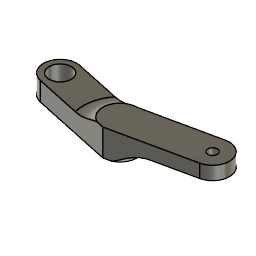
Left Control Arm (Autodesk Fusion 360 design; units mm, degrees)
Autodesk Fusion 360 part; units mm, degrees
sketch "Sketch1" plane through (0, 0, 0) normal (0, 0, 1) x (1, 0, 0)
  circle A0 centre (0, 0) radius 2.2
  circle A1 centre (28.829, 0) radius 0.9
  circle A2 centre (0, 0) radius 3.175
  circle A3 centre (28.829, 0) radius 3.175
  line L0 (28.161, 3.1039) -> (14.4145, 0.1454)
  line L1 (14.4145, 0.1454) -> (0.668, 3.1039)
  line L2 (29.497, -3.1039) -> (14.4145, -6.35)
  line L3 (14.4145, -6.35) -> (-0.668, -3.1039)
  dimension "d1" = 1.8
  dimension "d2" = 4.4
  dimension "d3" = 28.829
  dimension "d4" = 6.35
  dimension "d5" = 6.35
  dimension "d14" = 6.35
  constraint coincident A0.centre A2.centre
  constraint concentric A1 A3
  constraint horizontal A0.centre A1.centre
  constraint coincident A3 L0.start
  constraint coincident A2 L1.end
  constraint coincident A3 L2.start
  constraint parallel L0 L2
  constraint coincident A2 L3.end
  constraint tangent A2 L3
  constraint tangent A2 L1
  constraint tangent A3 L0
  constraint tangent A3 L2
  constraint parallel L1 L3
  constraint vertical L0.end L2.end
  measures "d1" diameter of A1
  measures "d2" diameter of A0
  measures "d3" distance of A0.centre A1.centre
  measures "d4" diameter of A3
  measures "d5" diameter of A2
  measures "d14" vertical distance of A1.centre L2.end
extrude "Extrude1" add sketch "Sketch1" along normal blind 2.54
sketch "Sketch3" plane through (0, 0, 0) normal (0, 0, -1) x (1, 0, 0)
  circle A0 centre (0, 0) radius 2.2
  circle A1 centre (28.829, 0) radius 0.9
  line L0 (0.668, -3.1039) -> (14.4145, -0.1454)
  line L1 (14.4145, -0.1454) -> (28.161, -3.1039)
  arc A2 (28.161, -3.1039) -> (29.497, 3.1039) centre (28.829, 0) ccw
  line L2 (29.497, 3.1039) -> (14.4145, 6.35)
  line L3 (14.4145, 6.35) -> (-0.668, 3.1039)
  arc A3 (-0.668, 3.1039) -> (0.668, -3.1039) centre (0, 0) ccw
  line L4 (14.4145, 6.35) -> (14.4145, -0.1454)
  circle A4 centre (0, 0) radius 3.175
  line L5 (14.4145, 6.35) -> (-0.668, 3.1039)
  line L6 (14.4145, -0.1454) -> (0.668, -3.1039)
  circle A5 centre (14.4145, 3.1023) radius 3.2477
  constraint coincident L2.end L3.start
  constraint coincident L0.end L1.start
  constraint coincident A0.centre A3.centre
  constraint coincident L3.end A3.start
  constraint tangent A4 L5
  constraint coincident L0.start A3.end
  constraint midpoint L4 A5.centre
  constraint coincident L2.end A5
extrude "Extrude3" add sketch "Sketch3" along normal blind 1.27 and the other way blind 1.905 contours L3 L4 L5 A5 | L2 L4 A5
sketch "Sketch2" plane through (0, 0, 0) normal (0, 0, -1) x (1, 0, 0)
  circle A0 centre (28.829, 0) radius 0.9
  arc A1 (28.161, -3.1039) -> (29.497, 3.1039) centre (28.829, 0) ccw
  circle A2 centre (0, 0) radius 2.0955
  circle A3 centre (0, 0) radius 3.175
  line L0 (14.4145, -0.1454) -> (28.161, -3.1039)
  line L1 (29.497, 3.1039) -> (15.7506, 6.0625)
  circle A4 centre (0, 0) radius 2.2
  line L2 (0.668, -3.1039) -> (14.4145, -0.1454)
  line L3 (13.0784, 6.0625) -> (-0.668, 3.1039)
  arc A5 (-0.668, 3.1039) -> (0.668, -3.1039) centre (0, 0) ccw
  arc A6 (14.4145, -0.1454) -> (15.7506, 6.0625) centre (14.4145, 3.1023) ccw
  arc A7 (13.0784, 6.0625) -> (14.4145, -0.1454) centre (14.4145, 3.1023) ccw
  dimension "d8" = 4.191
  dimension "d9" = 6.35
  measures "d8" diameter of A2
  measures "d9" diameter of A3
extrude "Extrude2" cut sketch "Sketch2" against normal blind 5.588 contours A3 L2 L3 A7 | A3 A5
sketch "Sketch4" plane through (0, 0, -1.27) normal (0, 0, -1) x (1, 0, 0)
  arc A0 (13.0784, 6.0625) -> (15.7506, 6.0625) centre (14.4145, 3.1023) ccw
  line L0 (15.7506, 6.0625) -> (14.4145, 6.35)
  line L1 (14.4145, 6.35) -> (13.0784, 6.0625)
  circle A1 centre (0, 0) radius 2.0955
  circle A2 centre (0, 0) radius 3.175
  line L2 (13.7465, 6.2062) -> (-0.668, 3.1039)
  line L3 (0.9727, -3.0223) -> (14.4145, -0.1454)
  dimension "d19" = 4.191
  dimension "d20" = 6.35
  dimension "d21" = 13.4418
  constraint coincident A1.centre A2.centre
  constraint concentric A1 A2
  constraint midpoint L1 L2.start
  constraint coincident A2 L2.end
  constraint tangent A2 L2
  constraint coincident A2 L3.start
  constraint midpoint A0 L3.end
  measures "d19" diameter of A1
  measures "d20" diameter of A2
  measures "d21" horizontal distance of L3.start L3.end
extrude "Extrude4" add sketch "Sketch4" along normal blind 1.27
extrude "Extrude5" add 1 faces at (4.0227, -3.2621, -1.27) along direction (0, 0, 1) blind 2.286
fillet "Fillet1" radius 5.08 1 edges at (11.2395, -2.419, 1.016)
fillet "Fillet2" radius 5.08 1 edges at (17.5895, -2.419, 0)
equation "d3 = 1.235 in - 0.1 in"
